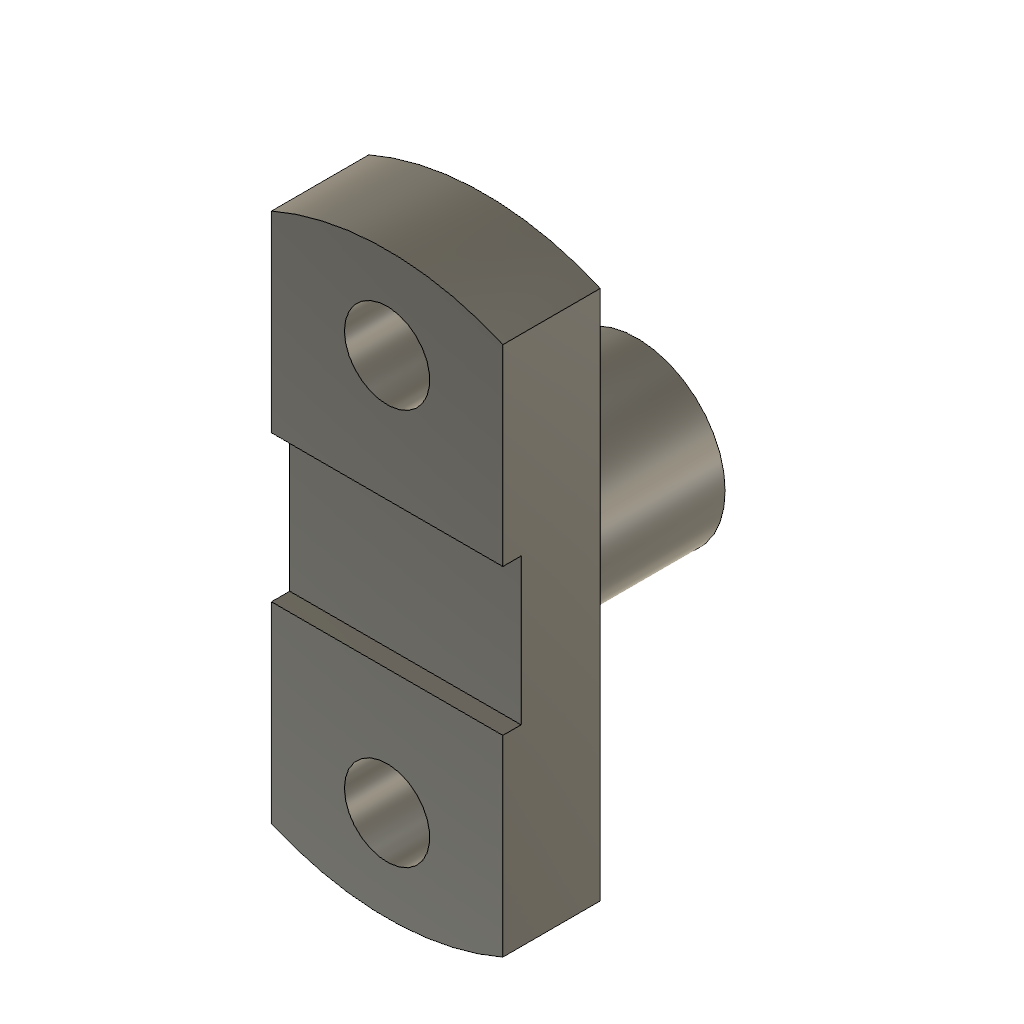
rodend (Autodesk Fusion 360 design; units mm, degrees)
part number: 2026-10-08-14-04-04-450
Autodesk Fusion 360 part; units mm, degrees
sketch "Sketch1" plane through (0, 0, 0) normal (0, 1, 0) x (1, 0, 0)
  line L0 (0, 0) -> (76, 0)
  line L1 (76, 0) -> (76, -190)
  line L2 (76, -190) -> (0, -190)
  line L3 (0, -190) -> (0, 0)
  line L4 (0, -190) -> (38, -190)
  line L5 (38, -190) -> (38, -160)
  line L6 (38, -160) -> (0, -160)
  line L7 (0, -160) -> (0, -190)
  circle A0 centre (38, -160) radius 14
  line L8 (38, -160) -> (38, -30)
  circle A1 centre (38, -30) radius 14
  dimension "d1" = 76
  dimension "d2" = 190
  dimension "d3" = 38
  dimension "d4" = 30
  dimension "d5" = 28
  dimension "d6" = 130
  dimension "d7" = 28
  constraint horizontal L0
  constraint vertical L1
  constraint horizontal L2
  constraint vertical L3
  constraint coincident L0.start L3.end
  constraint horizontal L4
  constraint vertical L5
  constraint horizontal L6
  constraint vertical L7
  constraint coincident L5.end L6.start
  constraint perpendicular L6 L8
  constraint coincident L8.end A1.centre
  measures "d1" distance of L0.start L0.end
  measures "d2" distance of L0.start L2.end
  measures "d3" distance of L2.end L4.end
  measures "d4" distance of L2.end L6.end
  measures "d5" diameter of A0
  measures "d6" distance of L5.end L8.end
  measures "d7" diameter of A1
extrude "Extrude1" add sketch "Sketch1" along normal blind 32 contours L0 L1 L2 L3 L5 L6 A0 | L2 L3 L4 L5 L6 L7 A0
sketch "Sketch2" plane through (76, 0, 0) normal (1, 0, 0) x (0, 1, 0)
  line L0 (0, 190) -> (0, 0)
  line L1 (0, 0) -> (32, 0)
  line L2 (32, 0) -> (32, 190)
  line L3 (32, 190) -> (0, 190)
  line L4 (0, 190) -> (0, 95)
  line L5 (6, 71) -> (-6, 71)
  line L6 (-6, 71) -> (-6, 119)
  line L7 (-6, 119) -> (6, 119)
  line L8 (6, 119) -> (6, 71)
  line L9 (6, 71) -> (-6, 119) construction
  line L10 (-6, 71) -> (6, 119) construction
  point P0 (0, 95)
  dimension "d10" = 95
  dimension "d11" = 12
  dimension "d12" = 48
  constraint coincident L0.start L3.end
  constraint perpendicular L3 L4
  constraint horizontal L5
  constraint perpendicular L5 L6
  constraint parallel L5 L7
  constraint parallel L6 L8
  constraint coincident L9 P0
  constraint coincident L10 P0
  constraint coincident P0 L4.end
  measures "d10" distance of L0.start P0
  measures "d11" distance of L6.end L7.end
  measures "d12" distance of L5.end L6.end
extrude "Extrude2" cut sketch "Sketch2" against normal blind 170 contours L0 L4 L5 L7 L8
sketch "Sketch3" plane through (0, 32, 0) normal (0, 1, 0) x (-1, 0, 0)
  circle A0 centre (-38, 160) radius 14
  circle A1 centre (-38, 30) radius 14
  line L0 (0, 0) -> (0, 190)
  line L1 (0, 190) -> (-76, 190)
  line L2 (-76, 190) -> (-76, 0)
  line L3 (-76, 0) -> (0, 0)
  line L4 (-76, 190) -> (-38, 190)
  line L5 (-76, 95) -> (-76, 190)
  circle A2 centre (-38, 95) radius 29
  dimension "d15" = 38
  dimension "d16" = 95
  dimension "d17" = 58
  constraint horizontal L4
  constraint vertical L5
  constraint coincident L1.end L2.start
  measures "d15" distance of L1.end L4.end
  measures "d16" distance of L1.end L5.start
  measures "d17" diameter of A2
extrude "Extrude3" add sketch "Sketch3" along normal blind 50 contours A2
sketch "Sketch4" plane through (0, 0, 0) normal (0, -1, 0) x (1, 0, 0)
  line L0 (0, 119) -> (76, 119)
  line L1 (76, 119) -> (76, 190)
  line L2 (76, 190) -> (0, 190)
  line L3 (0, 190) -> (0, 119)
  circle A0 centre (38, 160) radius 14
  line L4 (0, 190) -> (38, 190)
  line L5 (38, 190) -> (38, 95)
  line L6 (38, 95) -> (0, 95)
  line L7 (0, 95) -> (0, 190)
  circle A1 centre (38, 95) radius 95
  dimension "d20" = 38
  dimension "d21" = 95
  dimension "d22" = 190
  constraint horizontal L4
  constraint vertical L5
  constraint horizontal L6
  constraint vertical L7
  constraint coincident L2.end L3.start
  constraint coincident L5.end L6.start
  measures "d20" distance of L2.end L4.end
  measures "d21" distance of L2.end L6.end
  measures "d22" diameter of A1
extrude "Extrude4" cut sketch "Sketch4" against normal blind 170 contours L2 L3 L4 L7 A1 | L1 L2 A1
sketch "Sketch5" plane through (0, 0, 0) normal (0, -1, 0) x (1, 0, 0)
  circle A0 centre (38, 30) radius 14
  line L0 (76, 71) -> (0, 71)
  line L1 (0, 71) -> (0, 0)
  line L2 (0, 0) -> (76, 0)
  line L3 (76, 0) -> (76, 71)
  line L4 (0, 0) -> (38, 0)
  line L5 (38, 0) -> (38, 95)
  line L6 (38, 95) -> (0, 95)
  line L7 (0, 95) -> (0, 0)
  circle A1 centre (38, 95) radius 95
  dimension "d25" = 38
  dimension "d26" = 95
  dimension "d27" = 190
  constraint horizontal L4
  constraint vertical L5
  constraint horizontal L6
  constraint vertical L7
  constraint coincident L1.end L2.start
  constraint coincident L5.end L6.start
  measures "d25" distance of L1.end L4.end
  measures "d26" distance of L1.end L6.end
  measures "d27" diameter of A1
extrude "Extrude5" cut sketch "Sketch5" against normal blind 490 contours L2 L3 A1 | L1 L2 L4 L7 A1
